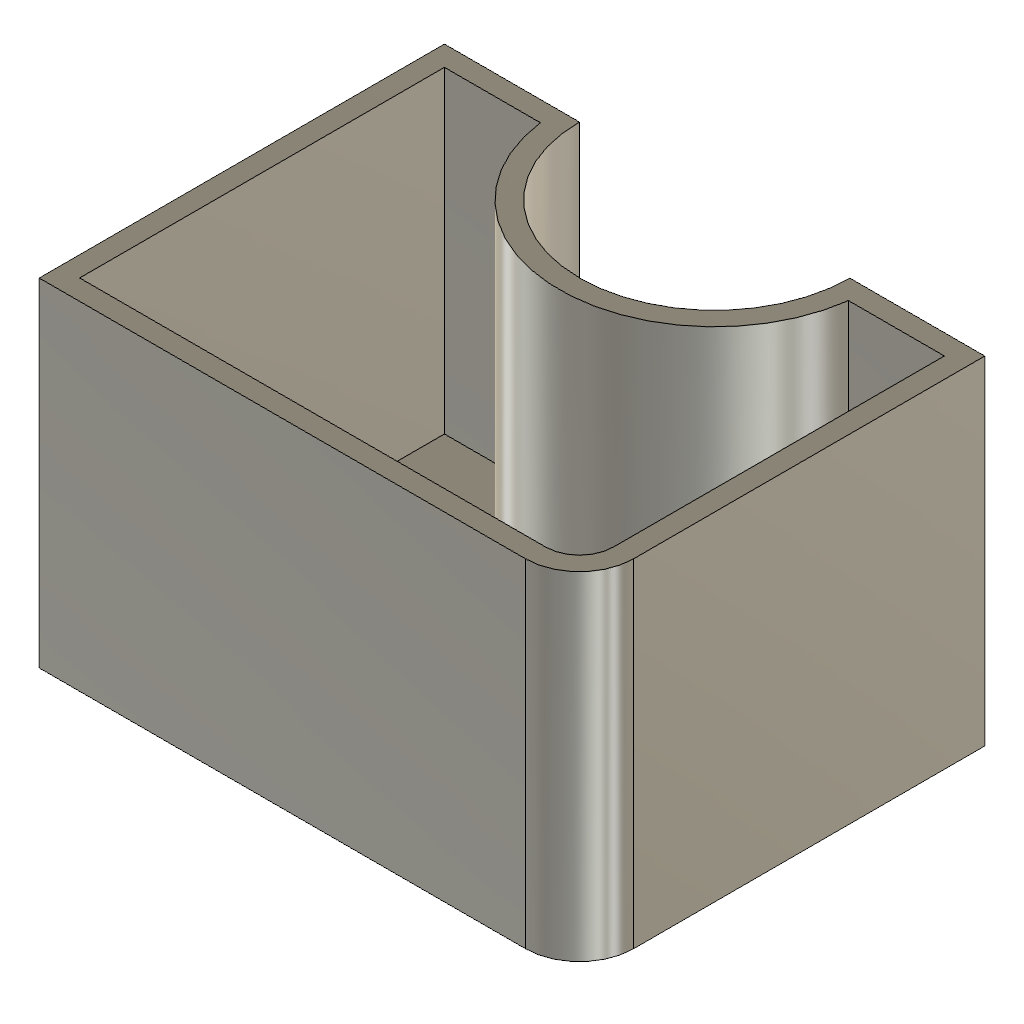
vendor_PartConcaveShell (Autodesk Fusion 360 design; units mm, degrees)
Autodesk Fusion 360 part; units mm, degrees
sketch "Notch sketch" plane through (0, 0, 0) normal (0, 0, 1) x (1, 0, 0)
  line L0 (0, 0) -> (40, 0)
  line L1 (40, 0) -> (40, 30)
  line L2 (40, 30) -> (30, 30)
  arc A0 (10, 30) -> (30, 30) centre (20, 30) ccw
  line L3 (10, 30) -> (0, 30)
  line L4 (0, 30) -> (0, 0)
extrude "Notch extrude" add sketch "Notch sketch" along normal blind 25
fillet "Corner Round" radius 4 1 edges at (40, 0, 12.5)
shell "Hollow" thickness 1.5 removed faces 1 at (18.4176, 6.676, 25)
equation "height = 20.0 mm"
